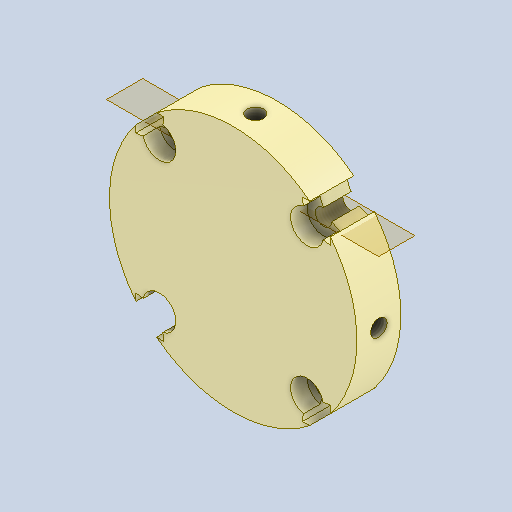
# Autodesk Inventor part: 零件1
Saved by Autodesk Inventor 2025 (Build 290162000, 162)
## iProperties
Created: 2026-11-03
Part Number: 零件1
Material: 尼龙 6/6
Document SubType Name: Modeling
Designer: test
Density: 1.13 g/cm^3
Appearance: 尼龙 6
Author: test
Autodesk Inventor part; units mm, degrees
ref_plane "YZ Plane" through (0, 0, 0) normal (1, 0, 0) x (0, 1, 0)
ref_plane "XY Plane" through (0, 0, 0) normal (0, 0, 1) x (1, 0, 0)
sketch "草图1" plane through (0, 0, 0) normal (0, 0, 1) x (1, 0, 0)
  circle A0 centre (0, 0) radius 22.5
  dimension "d0" = 45
  constraints: 1 centre point, 1 coincident
  measures "d0" diameter of A0
extrude "拉伸1" add sketch "草图1" along normal blind 8
sketch "草图2" plane through (0, 0, 8) normal (0, 0, 1) x (1, 0, 0)
  circle A0 centre (0, 0) radius 19
  line L0 (-13.435, -13.435) -> (13.435, -13.435)
  line L1 (13.435, -13.435) -> (13.435, 13.435)
  line L2 (13.435, 13.435) -> (-13.435, 13.435)
  line L3 (-13.435, 13.435) -> (-13.435, -13.435)
  line L4 (-13.435, -13.435) -> (13.435, 13.435) construction
  line L5 (13.435, -13.435) -> (-13.435, 13.435) construction
  circle A1 centre (-13.435, 13.435) radius 1.5
  circle A2 centre (13.435, 13.435) radius 1.5
  circle A3 centre (13.435, -13.435) radius 1.5
  circle A4 centre (-13.435, -13.435) radius 1.5
  dimension "d3" = 38
  dimension "d4" = 3
  dimension "d5" = 3
  dimension "d6" = 3
  dimension "d7" = 3
  constraints: 12 end point, 5 centre point, 4 coincident, 2 midpoint, 2 parallel, 2 perpendicular, 2 point on circle, 1 horizontal
  measures "d3" diameter of A0
  measures "d4" diameter of A1
  measures "d5" diameter of A2
  measures "d6" diameter of A3
  measures "d7" diameter of A4
extrude "拉伸2" cut sketch "草图2" against normal through all contours A2 L1 A0 | A0 A2 | A3 A0 | A0 L1 A3 | L2 A2 A0 | L1 A2 L2 | A0 A3 L0 | L0 A3 L1 | A1 L2 A0 | A0 A1 | A1 L3 L2 | A4 A0 | A0 L0 A4 | L0 L3 A4 | L3 A1 A0 | A0 A4 L3
ref_plane "工作平面1" through (0, 13.5, 0) normal (0, 1, 0) x (-1, 0, 0)
sketch "草图4" plane through (0, 13.5, 0) normal (0, 1, 0) x (-1, 0, 0)
  circle A0 centre (0, 4) radius 1.5
  line L0 (22.5, 8) -> (-22.5, 8) projected
  point P0 (0, 0)
  dimension "d13" = 3
  dimension "d14" = 4
  constraints: 1 centre point
  measures "d13" diameter of A0
  measures "d14" distance from line of A0.centre L0
extrude "拉伸3" cut sketch "草图4" along normal blind 10
thread "螺纹1" size "M3x0.5" designation "M3" class "6H" standard "GB Metric profile" length 15.103
pattern_circular "环形阵列1" count 4 over 360 about axis through (0, 0, 0) along (0, 0, 1) of "拉伸3"
thread "螺纹2" size "M3x0.5" designation "M3" class "6H" standard "GB Metric profile" length 15.103
thread "螺纹3" size "M3x0.5" designation "M3" class "6H" standard "GB Metric profile" length 15.103
thread "螺纹4" size "M3x0.5" designation "M3" class "6H" standard "GB Metric profile" length 15.103
thread "螺纹5" size "M3x0.5" designation "M3" class "6H" standard "GB Metric profile" length 15.103
sketch "草图5" plane through (0, 0, 8) normal (0, 0, 1) x (1, 0, 0)
  circle A0 centre (13.435, -13.435) radius 1.5 projected
  circle A1 centre (13.435, 13.435) radius 1.5 projected
  circle A2 centre (-13.435, -13.435) radius 1.5 projected
  circle A3 centre (-13.435, 13.435) radius 1.5 projected
  circle A4 centre (0, 0) radius 22.5 projected
  circle A5 centre (-13.435, -13.435) radius 3
  circle A6 centre (-13.435, 13.435) radius 3
  circle A7 centre (13.435, 13.435) radius 3
  circle A8 centre (13.435, -13.435) radius 3
  dimension "d30" = 6
  dimension "d31" = 6
  dimension "d32" = 6
  dimension "d33" = 6
  constraints: 4 centre point, 4 coincident
  measures "d30" diameter of A5
  measures "d31" diameter of A6
  measures "d32" diameter of A7
  measures "d33" diameter of A8
extrude "拉伸4" cut sketch "草图5" against normal blind 3 contours A5 | A6 | A7 | A8
sketch "草图6" plane through (0, 0, 8) normal (0, 0, 1) x (1, 0, 0)
  circle A0 centre (0, 0) radius 25
  line L0 (-17.6777, -17.6777) -> (17.6777, -17.6777)
  line L1 (17.6777, -17.6777) -> (17.6777, 17.6777)
  line L2 (17.6777, 17.6777) -> (-17.6777, 17.6777)
  line L3 (-17.6777, 17.6777) -> (-17.6777, -17.6777)
  line L4 (-17.6777, -17.6777) -> (17.6777, 17.6777) construction
  line L5 (17.6777, -17.6777) -> (-17.6777, 17.6777) construction
  circle A1 centre (-17.6777, 17.6777) radius 5.05
  circle A2 centre (17.6777, 17.6777) radius 5.05
  circle A3 centre (17.6777, -17.6777) radius 5.05
  circle A4 centre (-17.6777, -17.6777) radius 5.05
  point P0 (-12.6277, -17.6777)
  point P1 (-17.6777, -12.6277)
  point P2 (17.6777, -12.6277)
  point P3 (12.6277, -17.6777)
  point P4 (12.6277, 17.6777)
  point P5 (17.6777, 12.6277)
  point P6 (-17.6777, 12.6277)
  point P7 (-12.6277, 17.6777)
  dimension "d36" = 50
  dimension "d37" = 10.1
  dimension "d38" = 10.1
  dimension "d39" = 10.1
  dimension "d40" = 10.1
  constraints: 12 end point, 5 coincident, 4 centre point, 2 midpoint, 2 parallel, 2 perpendicular, 1 horizontal, 3 other
  measures "d37" diameter of A1
  measures "d38" diameter of A2
  measures "d39" diameter of A3
  measures "d40" diameter of A4
extrude "拉伸5" cut sketch "草图6" against normal blind 8 contours L1 A2 L2 | L0 A3 L1 | A1 L3 L2 | L0 L3 A4
